bicycle_rear_bracket_current (Autodesk Fusion 360 design; units mm, degrees)
part number: 2026-10-04-08-35-06-238
Autodesk Fusion 360 part; units mm, degrees
sketch "草图1" plane through (0, 0, 0) normal (0, 0, 1) x (1, 0, 0)
  circle A0 centre (0, 0) radius 19
  dimension "d17" = 38
  measures "d17" diameter of A0
extrude "Circular base 10mm" add sketch "草图1" along normal blind 10 makes body 1
ref_plane "工作平面1" through (0, 0, 10) normal (0, 0, 1) x (1, 0, 0)
sketch "草图2" plane through (0, 0, 10) normal (0, 0, 1) x (1, 0, 0)
  circle A0 centre (0, 0) radius 17
  dimension "d22" = 34
  measures "d22" diameter of A0
extrude "Circular recess with 2mm floor" cut sketch "草图2" against normal blind 8 bodies 1
fillet "Rounded circular rim" radius 0.5 2 edges at (-15.8496, 6.1475, 10) (-17.7142, -6.8707, 10) on bodies 1
sketch "草图3" plane through (0, 0, 0) normal (0, 0, 1) x (1, 0, 0)
  circle A0 centre (-11, 0) radius 1.75
  line L0 (0, 0) -> (-11, 0) construction
  circle A1 centre (11, 0) radius 1.75
  line L1 (0, 0) -> (11, 0) construction
  circle A2 centre (0, -11) radius 1.75
  line L2 (0, 0) -> (0, -11) construction
  circle A3 centre (0, 11) radius 1.75
  line L3 (0, 0) -> (0, 11) construction
  dimension "d27" = 3.5
  dimension "d28" = 11
  dimension "d29" = 3.5
  dimension "d30" = 11
  dimension "d31" = 3.5
  dimension "d32" = 11
  dimension "d33" = 3.5
  dimension "d34" = 11
  constraint horizontal L0
  constraint horizontal L1
  constraint vertical L2
  constraint vertical L3
  measures "d27" diameter of A0
  measures "d28" horizontal distance of L0.start A0.centre
  measures "d29" diameter of A1
  measures "d30" horizontal distance of L0.start A1.centre
  measures "d31" diameter of A2
  measures "d32" vertical distance of L0.start A2.centre
  measures "d33" diameter of A3
  measures "d34" vertical distance of L0.start A3.centre
extrude "Four 3.5mm base bores" cut sketch "草图3" along normal blind 2 bodies 1
sketch "草图4" plane through (0, 0, 0) normal (0, 0, 1) x (1, 0, 0)
  line L0 (-26.35, 24) -> (26.35, 24)
  line L1 (26.35, 24) -> (26.35, 29.5)
  line L2 (26.35, 29.5) -> (-26.35, 29.5)
  line L3 (-26.35, 29.5) -> (-26.35, 24)
  dimension "d37" = 26.35
  dimension "d38" = 24
  dimension "d39" = 52.7
  dimension "d40" = 5.5
  constraint horizontal L0
  constraint vertical L1
  constraint horizontal L2
  constraint vertical L3
  measures "d37" horizontal distance of origin L0.start
  measures "d38" vertical distance of origin L0.start
  measures "d39" horizontal distance of L0.start L0.end
  measures "d40" vertical distance of L0.end L1.end
extrude "Horizontal bar with flat rectangular section" add sketch "草图4" along normal blind 10 separate body makes body 2
sketch "草图5" plane through (0, 29.5, 0) normal (0, 1, 0) x (-1, 0, 0)
  line L0 (-26.35, 0) -> (26.35, 0)
  line L1 (26.35, 0) -> (26.35, 10)
  line L2 (26.35, 10) -> (-26.35, 10)
  line L3 (-26.35, 10) -> (-26.35, 0)
  circle A0 centre (21.075, 5) radius 2.725
  circle A1 centre (-21.075, 5) radius 2.725
  line L4 (21.075, 5) -> (-21.075, 5) construction
  dimension "d48" = 5.45
  dimension "d49" = 21.075
  dimension "d50" = 5
  dimension "d51" = 5.45
  dimension "d52" = 21.075
  constraint horizontal L4
  measures "d48" diameter of A0
  measures "d49" horizontal distance of origin A0.centre
  measures "d50" vertical distance of origin A0.centre
  measures "d51" diameter of A1
  measures "d52" horizontal distance of origin A1.centre
extrude "Two straight through bores - 5.5mm depth" cut sketch "草图5" against normal blind 5.5 contours A0 | A1 bodies 2
sketch "草图6" plane through (0, 0, 0) normal (0, 0, 1) x (1, 0, 0)
  line L0 (-17, 0) -> (17, 0)
  line L1 (17, 0) -> (17, 24.5)
  line L2 (17, 24.5) -> (-17, 24.5)
  line L3 (-17, 24.5) -> (-17, 0)
  line L4 (0, 0) -> (-17, 0) construction
  dimension "d55" = 17
  dimension "d56" = 34
  dimension "d57" = 24.5
  constraint horizontal L0
  constraint vertical L1
  constraint horizontal L2
  constraint vertical L3
  constraint horizontal L4
  measures "d55" horizontal distance of L4.start L0.start
  measures "d56" horizontal distance of L0.start L0.end
  measures "d57" vertical distance of L0.end L1.end
extrude "Flush planar connector" add sketch "草图6" along normal blind 10 separate body makes body 3
sketch "草图7" plane through (0, 0, 0) normal (0, 0, 1) x (1, 0, 0)
  circle A0 centre (0, 0) radius 18.5
  dimension "d60" = 18.5
  measures "d60" radius of A0
extrude "拉伸7" add sketch "草图7" along normal blind 10 separate body makes body 4
combine "Connector follows circular exterior only" operation cut target body 3 tool bodies 4
combine "Join exact circle and level bar" operation add target body 1 tool bodies 2 3
fillet "Smooth upper roots" radius 1 2 edges at (17, 24, 5) (-17, 24, 5) on bodies 1
move_body "Center true circular bracket on origin" bodies 1 to x (1, 0, 0) y (0, 1, 0) z (0, 0, 1) at (0, -5.25, -5)
equation "base_outer_d = 38 mm" comment "Circular base outer diameter"
equation "base_inner_d = 34 mm" comment "Circular recess diameter"
equation "base_height = 10 mm" comment "Base rim total height"
equation "base_floor = 2 mm" comment "Base plate thickness"
equation "base_hole_d = 3.5 mm" comment "Four original base mounting holes"
equation "base_hole_offset = 11 mm" comment "Base hole center radius"
equation "base_gap = 5 mm" comment "Circle top to crossbar lower edge"
equation "top_bar_length = 52.7 mm" comment "Crossbar length"
equation "top_bar_depth = 5.5 mm" comment "Bore-axis thickness"
equation "mount_hole_diameter = 5.45 mm" comment "Upper hole diameter"
equation "mount_hole_inner_gap = 36.7 mm" comment "Facing inner-wall spacing"
equation "mount_hole_spacing = mount_hole_inner_gap + mount_hole_diameter" comment "Upper hole center spacing"
equation "connector_width = 34 mm" comment "Solid connector width"
equation "connector_overlap_radius = 18.5 mm" comment "Clear of cup interior, overlap exterior rim"
equation "root_radius = 1 mm" comment "Smooth connector root transitions"
equation "rim_radius = 0.5 mm" comment "Rounded top rim matching original"
equation "d17 = base_outer_d"
equation "d18 = base_height"
equation "d20 = base_height"
equation "d22 = base_inner_d"
equation "d23 = -( base_height - base_floor )"
equation "d26 = rim_radius"
equation "d27 = base_hole_d"
equation "d28 = base_hole_offset"
equation "d29 = base_hole_d"
equation "d30 = base_hole_offset"
equation "d31 = base_hole_d"
equation "d32 = base_hole_offset"
equation "d33 = base_hole_d"
equation "d34 = base_hole_offset"
equation "d35 = base_floor"
equation "d37 = top_bar_length / 2"
equation "d38 = base_outer_d / 2 + base_gap"
equation "d39 = top_bar_length"
equation "d40 = top_bar_depth"
equation "d41 = base_height"
equation "d48 = mount_hole_diameter"
equation "d49 = mount_hole_spacing / 2"
equation "d50 = base_height / 2"
equation "d51 = mount_hole_diameter"
equation "d52 = mount_hole_spacing / 2"
equation "d55 = connector_width / 2"
equation "d56 = connector_width"
equation "d57 = base_outer_d / 2 + base_gap + 0.5 mm"
equation "d58 = base_height"
equation "d60 = connector_overlap_radius"
equation "d61 = base_height"
equation "d64 = root_radius"
named bodies: "Round base bracket - level bar", "Level mounting bar"
